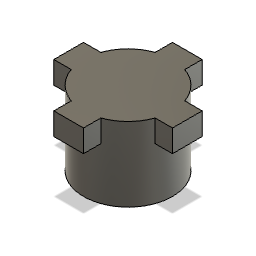
eje_pata (Autodesk Fusion 360 design; units mm, degrees)
Autodesk Fusion 360 part; units mm, degrees
sketch "Sketch1" plane through (0, 0, 0) normal (0, 1, 0) x (1, 0, 0)
  circle A0 centre (0, 0) radius 6
  dimension "d1" = 12
  constraint coincident A0.centre origin
  measures "d1" diameter of A0
extrude "Extrude1" add sketch "Sketch1" along normal blind 10
sketch "Sketch2" plane through (0, 10, 0) normal (0, 1, 0) x (-1, 0, 0)
  circle A0 centre (0, 0) radius 6
  line L0 (2, -8) -> (-2, -8)
  line L1 (-2, -8) -> (-2, -5.6569)
  line L2 (2, -5.6569) -> (2, -8)
  arc A1 (-2, -5.6569) -> (2, -5.6569) centre (0, 0) ccw
  dimension "d4" = 8
  dimension "d5" = 4
  dimension "d7" = 2
  constraint horizontal L0
  constraint vertical L1
  constraint vertical L2
  constraint coincident A0 L2.start
  constraint coincident A0 L1.end
  constraint coincident A0.centre A1.centre
  measures "d4" distance of A0.centre L0
  measures "d5" distance of L1 L2
  measures "d7" distance of A0.centre L1
extrude "Extrude2" add sketch "Sketch2" against normal blind 3 contours A0 L0 L1 L2 A1
pattern_circular "C-Pattern1" count 4 over 360 about axis through (0, 1.75, 0) along (0, 1, 0) of "Extrude2"
